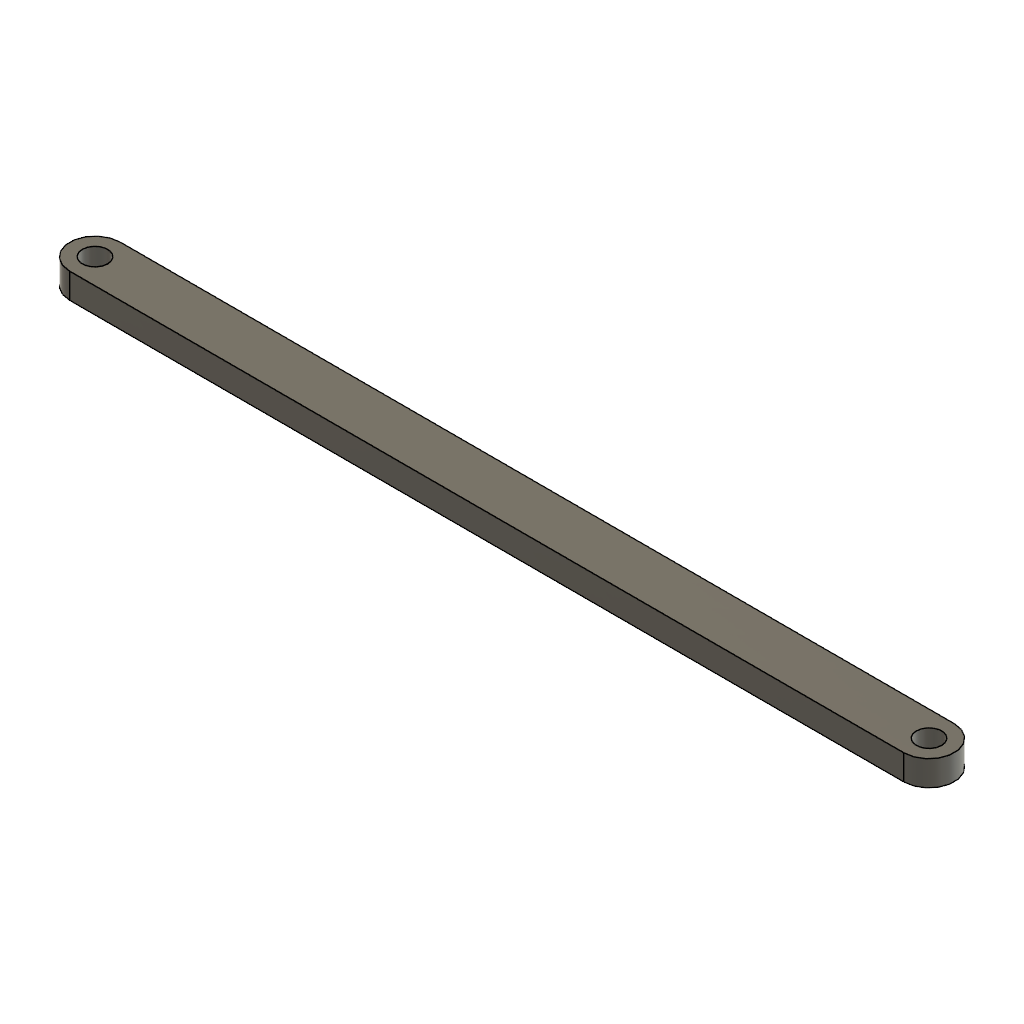
link 5 (Autodesk Fusion 360 design; units mm, degrees)
part number: 2026-11-18-20-16-29-603
Autodesk Fusion 360 part; units mm, degrees
sketch "Sketch1" plane through (0, 0, 0) normal (0, 1, 0) x (1, 0, 0)
  line L0 (0, -5) -> (165, -5)
  line L1 (0, 5) -> (165, 5)
  arc A0 (0, 5) -> (0, -5) centre (0, 0) ccw
  arc A1 (165, -5) -> (165, 5) centre (165, 0) ccw
  circle A2 centre (0, 0) radius 2.5
  circle A3 centre (165, 0) radius 2.5
  dimension "d1" = 10
  dimension "d2" = 165
  dimension "d3" = 5
  dimension "d4" = 10
  dimension "d5" = 5
  dimension "d6" = 5
  constraint coincident A0.centre A2.centre
  constraint horizontal L0
  constraint horizontal L1
  constraint concentric A0 A2
  constraint concentric A1 A3
  measures "d1" diameter of A0
  measures "d2" distance of L0.start L0.end
  measures "d3" distance of L0.end A1.centre
  measures "d4" distance of L0 L1
  measures "d5" diameter of A2
  measures "d6" diameter of A3
extrude "Extrude1" add sketch "Sketch1" along normal blind 5
